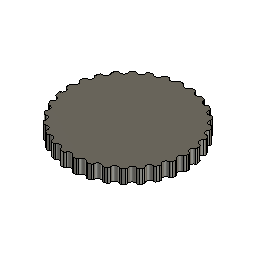
knob_ec12_3dprint (Autodesk Fusion 360 design; units mm, degrees)
Autodesk Fusion 360 part; units mm, degrees
sketch "Sketch1" plane through (0, 0, 0) normal (0, 0, 1) x (1, 0, 0)
  circle A0 centre (0, 0) radius 17.5
  circle A1 centre (0.0503, 17.4999) radius 1
  circle A2 centre (-3.5893, 17.128) radius 1
  circle A3 centre (-7.0719, 16.0074) radius 1
  circle A4 centre (-10.2455, 14.1873) radius 1
  circle A5 centre (-12.9713, 11.7471) radius 1
  circle A6 centre (-15.1302, 8.7935) radius 1
  circle A7 centre (-16.6279, 5.4556) radius 1
  circle A8 centre (-17.3988, 1.8793) radius 1
  circle A9 centre (-17.4093, -1.7792) radius 1
  circle A10 centre (-16.659, -5.3599) radius 1
  circle A11 centre (-15.1805, -8.7064) radius 1
  circle A12 centre (-13.0386, -11.6724) radius 1
  circle A13 centre (-10.3269, -14.1282) radius 1
  circle A14 centre (-7.1638, -15.9665) radius 1
  circle A15 centre (-3.6876, -17.1071) radius 1
  circle A16 centre (-0.0503, -17.4999) radius 1
  circle A17 centre (3.5893, -17.128) radius 1
  circle A18 centre (7.0719, -16.0074) radius 1
  circle A19 centre (10.2455, -14.1873) radius 1
  circle A20 centre (12.9713, -11.7471) radius 1
  circle A21 centre (15.1302, -8.7935) radius 1
  circle A22 centre (16.6279, -5.4556) radius 1
  circle A23 centre (17.3988, -1.8793) radius 1
  circle A24 centre (17.4093, 1.7792) radius 1
  circle A25 centre (16.659, 5.3599) radius 1
  circle A26 centre (15.1805, 8.7064) radius 1
  circle A27 centre (13.0386, 11.6724) radius 1
  circle A28 centre (10.3269, 14.1282) radius 1
  circle A29 centre (7.1638, 15.9665) radius 1
  circle A30 centre (3.6876, 17.1071) radius 1
  dimension "d1" = 35
  dimension "d12" = 2
  dimension "d14" = 360
  constraint coincident A0.centre origin
  constraint coincident A0 A1.centre
  measures "d1" diameter of A0
  measures "d12" diameter of A1
extrude "Extrude1" add sketch "Sketch1" along normal blind 4 contours A0 A1 A2 A3 A4 A5 A6 A7 A8 A9 A10 A11 A12 A13 A14 A15 A16 A17 A18 A19 A20 A21 A22 A23 A24 A25 A26 A27 A28 A29 A30
sketch "Sketch2" plane through (0, 0, 0) normal (0, 0, -1) x (1, 0, 0)
  circle A0 centre (0, 0) radius 3.025
  line L0 (2.2244, 2.05) -> (2.2244, -2.05)
  line L1 (0, 0) -> (2.2244, 2.05)
  line L2 (0, 0) -> (2.2244, -2.05)
  circle A1 centre (2.0774, 1.9145) radius 1.05
  circle A2 centre (2.0774, -1.9145) radius 1.05
  arc A3 (8.0641, -15.5313) -> (9.503, -14.695) centre (0, 0) ccw
  arc A4 (11.117, -13.5152) -> (9.503, -14.695) centre (10.3269, -14.1282) ccw
  arc A5 (11.117, -13.5152) -> (12.3506, -12.3981) centre (0, 0) ccw
  arc A6 (13.6841, -10.9085) -> (12.3506, -12.3981) centre (13.0386, -11.6724) ccw
  arc A7 (13.6841, -10.9085) -> (14.6584, -9.5593) centre (0, 0) ccw
  arc A8 (15.653, -7.8251) -> (14.6584, -9.5593) centre (15.1805, -8.7064) ccw
  arc A9 (15.653, -7.8251) -> (16.3256, -6.3028) centre (0, 0) ccw
  arc A10 (16.9379, -4.3996) -> (16.3256, -6.3028) centre (16.659, -5.3599) ccw
  arc A11 (16.9379, -4.3996) -> (17.2793, -2.7707) centre (0, 0) ccw
  arc A12 (17.4825, -0.7819) -> (17.2793, -2.7707) centre (17.4093, -1.7792) ccw
  arc A13 (17.4825, -0.7819) -> (17.4777, 0.8824) centre (0, 0) ccw
  arc A14 (17.2631, 2.87) -> (17.4777, 0.8824) centre (17.3988, 1.8793) ccw
  arc A15 (17.2631, 2.87) -> (16.9124, 4.4969) centre (0, 0) ccw
  arc A16 (16.2891, 6.3965) -> (16.9124, 4.4969) centre (16.6279, 5.4556) ccw
  arc A17 (16.2891, 6.3965) -> (15.6078, 7.9149) centre (0, 0) ccw
  arc A18 (14.6033, 9.6434) -> (15.6078, 7.9149) centre (15.1302, 8.7935) ccw
  arc A19 (14.6033, 9.6434) -> (13.6211, 10.987) centre (0, 0) ccw
  arc A20 (12.2792, 12.4688) -> (13.6211, 10.987) centre (12.9713, 11.7471) ccw
  arc A21 (12.2792, 12.4688) -> (11.0392, 13.5789) centre (0, 0) ccw
  arc A22 (9.4184, 14.7494) -> (11.0392, 13.5789) centre (10.2455, 14.1873) ccw
  arc A23 (9.4184, 14.7494) -> (7.9747, 15.5774) centre (0, 0) ccw
  arc A24 (6.146, 16.3852) -> (7.9747, 15.5774) centre (7.0719, 16.0074) ccw
  arc A25 (6.146, 16.3852) -> (4.5617, 16.895) centre (0, 0) ccw
  arc A26 (2.605, 17.305) -> (4.5617, 16.895) centre (3.5893, 17.128) ccw
  arc A27 (2.605, 17.305) -> (0.9494, 17.4742) centre (0, 0) ccw
  arc A28 (-1.0498, 17.4685) -> (0.9494, 17.4742) centre (-0.0503, 17.4999) ccw
  arc A29 (-1.0498, 17.4685) -> (-2.7045, 17.2898) centre (0, 0) ccw
  arc A30 (-4.6588, 16.8685) -> (-2.7045, 17.2898) centre (-3.6876, 17.1071) ccw
  arc A31 (-4.6588, 16.8685) -> (-6.2401, 16.3497) centre (0, 0) ccw
  arc A32 (-8.0641, 15.5313) -> (-6.2401, 16.3497) centre (-7.1638, 15.9665) ccw
  arc A33 (-8.0641, 15.5313) -> (-9.503, 14.695) centre (0, 0) ccw
  arc A34 (-11.117, 13.5152) -> (-9.503, 14.695) centre (-10.3269, 14.1282) ccw
  arc A35 (-11.117, 13.5152) -> (-12.3506, 12.3981) centre (0, 0) ccw
  arc A36 (-13.6841, 10.9085) -> (-12.3506, 12.3981) centre (-13.0386, 11.6724) ccw
  arc A37 (-13.6841, 10.9085) -> (-14.6584, 9.5593) centre (0, 0) ccw
  arc A38 (-15.653, 7.8251) -> (-14.6584, 9.5593) centre (-15.1805, 8.7064) ccw
  arc A39 (-15.653, 7.8251) -> (-16.3256, 6.3028) centre (0, 0) ccw
  arc A40 (-16.9379, 4.3996) -> (-16.3256, 6.3028) centre (-16.659, 5.3599) ccw
  arc A41 (-16.9379, 4.3996) -> (-17.2793, 2.7707) centre (0, 0) ccw
  arc A42 (-17.4825, 0.7819) -> (-17.2793, 2.7707) centre (-17.4093, 1.7792) ccw
  arc A43 (-17.4825, 0.7819) -> (-17.4777, -0.8824) centre (0, 0) ccw
  arc A44 (-17.2631, -2.87) -> (-17.4777, -0.8824) centre (-17.3988, -1.8793) ccw
  arc A45 (-17.2631, -2.87) -> (-16.9124, -4.4969) centre (0, 0) ccw
  arc A46 (-16.2891, -6.3965) -> (-16.9124, -4.4969) centre (-16.6279, -5.4556) ccw
  arc A47 (-16.2891, -6.3965) -> (-15.6078, -7.9149) centre (0, 0) ccw
  arc A48 (-14.6033, -9.6434) -> (-15.6078, -7.9149) centre (-15.1302, -8.7935) ccw
  arc A49 (-14.6033, -9.6434) -> (-13.6211, -10.987) centre (0, 0) ccw
  arc A50 (-12.2792, -12.4688) -> (-13.6211, -10.987) centre (-12.9713, -11.7471) ccw
  arc A51 (-12.2792, -12.4688) -> (-11.0392, -13.5789) centre (0, 0) ccw
  arc A52 (-9.4184, -14.7494) -> (-11.0392, -13.5789) centre (-10.2455, -14.1873) ccw
  arc A53 (-9.4184, -14.7494) -> (-7.9747, -15.5774) centre (0, 0) ccw
  arc A54 (-6.146, -16.3852) -> (-7.9747, -15.5774) centre (-7.0719, -16.0074) ccw
  arc A55 (-6.146, -16.3852) -> (-4.5617, -16.895) centre (0, 0) ccw
  arc A56 (-2.605, -17.305) -> (-4.5617, -16.895) centre (-3.5893, -17.128) ccw
  arc A57 (-2.605, -17.305) -> (-0.9494, -17.4742) centre (0, 0) ccw
  arc A58 (1.0498, -17.4685) -> (-0.9494, -17.4742) centre (0.0503, -17.4999) ccw
  arc A59 (1.0498, -17.4685) -> (2.7045, -17.2898) centre (0, 0) ccw
  arc A60 (4.6588, -16.8685) -> (2.7045, -17.2898) centre (3.6876, -17.1071) ccw
  arc A61 (4.6588, -16.8685) -> (6.2401, -16.3497) centre (0, 0) ccw
  arc A62 (8.0641, -15.5313) -> (6.2401, -16.3497) centre (7.1638, -15.9665) ccw
  dimension "d4" = 6.05
  dimension "d5" = 4.1
  dimension "d6" = 2.1
  dimension "d7" = 0.2
  dimension "d8" = 2.1
  dimension "d9" = 0.2
  constraint concentric A0 A3
  constraint coincident A0 L0.start
  constraint coincident A0 L0.end
  constraint vertical L0
  constraint coincident A0.centre L1.start
  constraint coincident L1 A1.centre
  constraint coincident L2 A2.centre
  measures "d4" diameter of A0
  measures "d5" distance of L0.start L0.end
  measures "d6" diameter of A1
  measures "d7" distance of L0.start A1.centre
  measures "d8" diameter of A2
  measures "d9" distance of L0.end A2.centre
extrude "Extrude2" cut sketch "Sketch2" against normal blind 2.6 contours A0 L0 A1 | A0 A1 | A0 A2 | A0 L0 A2 | A0 L1 A1 | L0 L1 A1 | L0 L1 L2 A1 A2 | L0 L2 A2 | A0 L2 A2 | A0 L1 L2 A1 A2
sketch "Sketch3" plane through (0, 0, 0) normal (0, 0, -1) x (1, 0, 0)
  arc A0 (1.3746, 2.6946) -> (1.3746, -2.6946) centre (0, 0) ccw
  arc A1 (2.2244, 0.8748) -> (1.3746, 2.6946) centre (2.0774, 1.9145) ccw
  line L0 (2.2244, 0.8748) -> (2.2244, -0.8748)
  arc A2 (1.3746, -2.6946) -> (2.2244, -0.8748) centre (2.0774, -1.9145) ccw
  arc A3 (8.0641, -15.5313) -> (9.503, -14.695) centre (0, 0) ccw
  arc A4 (11.117, -13.5152) -> (9.503, -14.695) centre (10.3269, -14.1282) ccw
  arc A5 (11.117, -13.5152) -> (12.3506, -12.3981) centre (0, 0) ccw
  arc A6 (13.6841, -10.9085) -> (12.3506, -12.3981) centre (13.0386, -11.6724) ccw
  arc A7 (13.6841, -10.9085) -> (14.6584, -9.5593) centre (0, 0) ccw
  arc A8 (15.653, -7.8251) -> (14.6584, -9.5593) centre (15.1805, -8.7064) ccw
  arc A9 (15.653, -7.8251) -> (16.3256, -6.3028) centre (0, 0) ccw
  arc A10 (16.9379, -4.3996) -> (16.3256, -6.3028) centre (16.659, -5.3599) ccw
  arc A11 (16.9379, -4.3996) -> (17.2793, -2.7707) centre (0, 0) ccw
  arc A12 (17.4825, -0.7819) -> (17.2793, -2.7707) centre (17.4093, -1.7792) ccw
  arc A13 (17.4825, -0.7819) -> (17.4777, 0.8824) centre (0, 0) ccw
  arc A14 (17.2631, 2.87) -> (17.4777, 0.8824) centre (17.3988, 1.8793) ccw
  arc A15 (17.2631, 2.87) -> (16.9124, 4.4969) centre (0, 0) ccw
  arc A16 (16.2891, 6.3965) -> (16.9124, 4.4969) centre (16.6279, 5.4556) ccw
  arc A17 (16.2891, 6.3965) -> (15.6078, 7.9149) centre (0, 0) ccw
  arc A18 (14.6033, 9.6434) -> (15.6078, 7.9149) centre (15.1302, 8.7935) ccw
  arc A19 (14.6033, 9.6434) -> (13.6211, 10.987) centre (0, 0) ccw
  arc A20 (12.2792, 12.4688) -> (13.6211, 10.987) centre (12.9713, 11.7471) ccw
  arc A21 (12.2792, 12.4688) -> (11.0392, 13.5789) centre (0, 0) ccw
  arc A22 (9.4184, 14.7494) -> (11.0392, 13.5789) centre (10.2455, 14.1873) ccw
  arc A23 (9.4184, 14.7494) -> (7.9747, 15.5774) centre (0, 0) ccw
  arc A24 (6.146, 16.3852) -> (7.9747, 15.5774) centre (7.0719, 16.0074) ccw
  arc A25 (6.146, 16.3852) -> (4.5617, 16.895) centre (0, 0) ccw
  arc A26 (2.605, 17.305) -> (4.5617, 16.895) centre (3.5893, 17.128) ccw
  arc A27 (2.605, 17.305) -> (0.9494, 17.4742) centre (0, 0) ccw
  arc A28 (-1.0498, 17.4685) -> (0.9494, 17.4742) centre (-0.0503, 17.4999) ccw
  arc A29 (-1.0498, 17.4685) -> (-2.7045, 17.2898) centre (0, 0) ccw
  arc A30 (-4.6588, 16.8685) -> (-2.7045, 17.2898) centre (-3.6876, 17.1071) ccw
  arc A31 (-4.6588, 16.8685) -> (-6.2401, 16.3497) centre (0, 0) ccw
  arc A32 (-8.0641, 15.5313) -> (-6.2401, 16.3497) centre (-7.1638, 15.9665) ccw
  arc A33 (-8.0641, 15.5313) -> (-9.503, 14.695) centre (0, 0) ccw
  arc A34 (-11.117, 13.5152) -> (-9.503, 14.695) centre (-10.3269, 14.1282) ccw
  arc A35 (-11.117, 13.5152) -> (-12.3506, 12.3981) centre (0, 0) ccw
  arc A36 (-13.6841, 10.9085) -> (-12.3506, 12.3981) centre (-13.0386, 11.6724) ccw
  arc A37 (-13.6841, 10.9085) -> (-14.6584, 9.5593) centre (0, 0) ccw
  arc A38 (-15.653, 7.8251) -> (-14.6584, 9.5593) centre (-15.1805, 8.7064) ccw
  arc A39 (-15.653, 7.8251) -> (-16.3256, 6.3028) centre (0, 0) ccw
  arc A40 (-16.9379, 4.3996) -> (-16.3256, 6.3028) centre (-16.659, 5.3599) ccw
  arc A41 (-16.9379, 4.3996) -> (-17.2793, 2.7707) centre (0, 0) ccw
  arc A42 (-17.4825, 0.7819) -> (-17.2793, 2.7707) centre (-17.4093, 1.7792) ccw
  arc A43 (-17.4825, 0.7819) -> (-17.4777, -0.8824) centre (0, 0) ccw
  arc A44 (-17.2631, -2.87) -> (-17.4777, -0.8824) centre (-17.3988, -1.8793) ccw
  arc A45 (-17.2631, -2.87) -> (-16.9124, -4.4969) centre (0, 0) ccw
  arc A46 (-16.2891, -6.3965) -> (-16.9124, -4.4969) centre (-16.6279, -5.4556) ccw
  arc A47 (-16.2891, -6.3965) -> (-15.6078, -7.9149) centre (0, 0) ccw
  arc A48 (-14.6033, -9.6434) -> (-15.6078, -7.9149) centre (-15.1302, -8.7935) ccw
  arc A49 (-14.6033, -9.6434) -> (-13.6211, -10.987) centre (0, 0) ccw
  arc A50 (-12.2792, -12.4688) -> (-13.6211, -10.987) centre (-12.9713, -11.7471) ccw
  arc A51 (-12.2792, -12.4688) -> (-11.0392, -13.5789) centre (0, 0) ccw
  arc A52 (-9.4184, -14.7494) -> (-11.0392, -13.5789) centre (-10.2455, -14.1873) ccw
  arc A53 (-9.4184, -14.7494) -> (-7.9747, -15.5774) centre (0, 0) ccw
  arc A54 (-6.146, -16.3852) -> (-7.9747, -15.5774) centre (-7.0719, -16.0074) ccw
  arc A55 (-6.146, -16.3852) -> (-4.5617, -16.895) centre (0, 0) ccw
  arc A56 (-2.605, -17.305) -> (-4.5617, -16.895) centre (-3.5893, -17.128) ccw
  arc A57 (-2.605, -17.305) -> (-0.9494, -17.4742) centre (0, 0) ccw
  arc A58 (1.0498, -17.4685) -> (-0.9494, -17.4742) centre (0.0503, -17.4999) ccw
  arc A59 (1.0498, -17.4685) -> (2.7045, -17.2898) centre (0, 0) ccw
  arc A60 (4.6588, -16.8685) -> (2.7045, -17.2898) centre (3.6876, -17.1071) ccw
  arc A61 (4.6588, -16.8685) -> (6.2401, -16.3497) centre (0, 0) ccw
  arc A62 (8.0641, -15.5313) -> (6.2401, -16.3497) centre (7.1638, -15.9665) ccw
  circle A63 centre (0, 0) radius 5
  constraint concentric A0 A63
sketch "Sketch4" plane through (0, 0, 0) normal (0, 0, -1) x (1, 0, 0)
  arc A0 (1.3746, 2.6946) -> (1.3746, -2.6946) centre (0, 0) ccw
  arc A1 (2.2244, 0.8748) -> (1.3746, 2.6946) centre (2.0774, 1.9145) ccw
  line L0 (2.2244, 0.8748) -> (2.2244, -0.8748)
  arc A2 (1.3746, -2.6946) -> (2.2244, -0.8748) centre (2.0774, -1.9145) ccw
  arc A3 (8.0641, -15.5313) -> (9.503, -14.695) centre (0, 0) ccw
  arc A4 (11.117, -13.5152) -> (9.503, -14.695) centre (10.3269, -14.1282) ccw
  arc A5 (11.117, -13.5152) -> (12.3506, -12.3981) centre (0, 0) ccw
  arc A6 (13.6841, -10.9085) -> (12.3506, -12.3981) centre (13.0386, -11.6724) ccw
  arc A7 (13.6841, -10.9085) -> (14.6584, -9.5593) centre (0, 0) ccw
  arc A8 (15.653, -7.8251) -> (14.6584, -9.5593) centre (15.1805, -8.7064) ccw
  arc A9 (15.653, -7.8251) -> (16.3256, -6.3028) centre (0, 0) ccw
  arc A10 (16.9379, -4.3996) -> (16.3256, -6.3028) centre (16.659, -5.3599) ccw
  arc A11 (16.9379, -4.3996) -> (17.2793, -2.7707) centre (0, 0) ccw
  arc A12 (17.4825, -0.7819) -> (17.2793, -2.7707) centre (17.4093, -1.7792) ccw
  arc A13 (17.4825, -0.7819) -> (17.4777, 0.8824) centre (0, 0) ccw
  arc A14 (17.2631, 2.87) -> (17.4777, 0.8824) centre (17.3988, 1.8793) ccw
  arc A15 (17.2631, 2.87) -> (16.9124, 4.4969) centre (0, 0) ccw
  arc A16 (16.2891, 6.3965) -> (16.9124, 4.4969) centre (16.6279, 5.4556) ccw
  arc A17 (16.2891, 6.3965) -> (15.6078, 7.9149) centre (0, 0) ccw
  arc A18 (14.6033, 9.6434) -> (15.6078, 7.9149) centre (15.1302, 8.7935) ccw
  arc A19 (14.6033, 9.6434) -> (13.6211, 10.987) centre (0, 0) ccw
  arc A20 (12.2792, 12.4688) -> (13.6211, 10.987) centre (12.9713, 11.7471) ccw
  arc A21 (12.2792, 12.4688) -> (11.0392, 13.5789) centre (0, 0) ccw
  arc A22 (9.4184, 14.7494) -> (11.0392, 13.5789) centre (10.2455, 14.1873) ccw
  arc A23 (9.4184, 14.7494) -> (7.9747, 15.5774) centre (0, 0) ccw
  arc A24 (6.146, 16.3852) -> (7.9747, 15.5774) centre (7.0719, 16.0074) ccw
  arc A25 (6.146, 16.3852) -> (4.5617, 16.895) centre (0, 0) ccw
  arc A26 (2.605, 17.305) -> (4.5617, 16.895) centre (3.5893, 17.128) ccw
  arc A27 (2.605, 17.305) -> (0.9494, 17.4742) centre (0, 0) ccw
  arc A28 (-1.0498, 17.4685) -> (0.9494, 17.4742) centre (-0.0503, 17.4999) ccw
  arc A29 (-1.0498, 17.4685) -> (-2.7045, 17.2898) centre (0, 0) ccw
  arc A30 (-4.6588, 16.8685) -> (-2.7045, 17.2898) centre (-3.6876, 17.1071) ccw
  arc A31 (-4.6588, 16.8685) -> (-6.2401, 16.3497) centre (0, 0) ccw
  arc A32 (-8.0641, 15.5313) -> (-6.2401, 16.3497) centre (-7.1638, 15.9665) ccw
  arc A33 (-8.0641, 15.5313) -> (-9.503, 14.695) centre (0, 0) ccw
  arc A34 (-11.117, 13.5152) -> (-9.503, 14.695) centre (-10.3269, 14.1282) ccw
  arc A35 (-11.117, 13.5152) -> (-12.3506, 12.3981) centre (0, 0) ccw
  arc A36 (-13.6841, 10.9085) -> (-12.3506, 12.3981) centre (-13.0386, 11.6724) ccw
  arc A37 (-13.6841, 10.9085) -> (-14.6584, 9.5593) centre (0, 0) ccw
  arc A38 (-15.653, 7.8251) -> (-14.6584, 9.5593) centre (-15.1805, 8.7064) ccw
  arc A39 (-15.653, 7.8251) -> (-16.3256, 6.3028) centre (0, 0) ccw
  arc A40 (-16.9379, 4.3996) -> (-16.3256, 6.3028) centre (-16.659, 5.3599) ccw
  arc A41 (-16.9379, 4.3996) -> (-17.2793, 2.7707) centre (0, 0) ccw
  arc A42 (-17.4825, 0.7819) -> (-17.2793, 2.7707) centre (-17.4093, 1.7792) ccw
  arc A43 (-17.4825, 0.7819) -> (-17.4777, -0.8824) centre (0, 0) ccw
  arc A44 (-17.2631, -2.87) -> (-17.4777, -0.8824) centre (-17.3988, -1.8793) ccw
  arc A45 (-17.2631, -2.87) -> (-16.9124, -4.4969) centre (0, 0) ccw
  arc A46 (-16.2891, -6.3965) -> (-16.9124, -4.4969) centre (-16.6279, -5.4556) ccw
  arc A47 (-16.2891, -6.3965) -> (-15.6078, -7.9149) centre (0, 0) ccw
  arc A48 (-14.6033, -9.6434) -> (-15.6078, -7.9149) centre (-15.1302, -8.7935) ccw
  arc A49 (-14.6033, -9.6434) -> (-13.6211, -10.987) centre (0, 0) ccw
  arc A50 (-12.2792, -12.4688) -> (-13.6211, -10.987) centre (-12.9713, -11.7471) ccw
  arc A51 (-12.2792, -12.4688) -> (-11.0392, -13.5789) centre (0, 0) ccw
  arc A52 (-9.4184, -14.7494) -> (-11.0392, -13.5789) centre (-10.2455, -14.1873) ccw
  arc A53 (-9.4184, -14.7494) -> (-7.9747, -15.5774) centre (0, 0) ccw
  arc A54 (-6.146, -16.3852) -> (-7.9747, -15.5774) centre (-7.0719, -16.0074) ccw
  arc A55 (-6.146, -16.3852) -> (-4.5617, -16.895) centre (0, 0) ccw
  arc A56 (-2.605, -17.305) -> (-4.5617, -16.895) centre (-3.5893, -17.128) ccw
  arc A57 (-2.605, -17.305) -> (-0.9494, -17.4742) centre (0, 0) ccw
  arc A58 (1.0498, -17.4685) -> (-0.9494, -17.4742) centre (0.0503, -17.4999) ccw
  arc A59 (1.0498, -17.4685) -> (2.7045, -17.2898) centre (0, 0) ccw
  arc A60 (4.6588, -16.8685) -> (2.7045, -17.2898) centre (3.6876, -17.1071) ccw
  arc A61 (4.6588, -16.8685) -> (6.2401, -16.3497) centre (0, 0) ccw
  arc A62 (8.0641, -15.5313) -> (6.2401, -16.3497) centre (7.1638, -15.9665) ccw
  circle A63 centre (0, 0) radius 11
  circle A64 centre (0, -11) radius 2.5
  circle A65 centre (0, 11) radius 2.5
  circle A66 centre (-11, 0) radius 2.5
  circle A67 centre (11, 0) radius 2.5
  point P0 (-0.3876, 0)
  dimension "d17" = 22
  dimension "d39" = 5
  dimension "d40" = 5
  dimension "d41" = 5
  dimension "d42" = 5
  dimension "d45" = 2.612
  dimension "d46" = 0.3876
  constraint concentric A0 A63
  constraint coincident A63 A64.centre
  constraint coincident A63 A65.centre
  constraint coincident A63 A66.centre
  constraint coincident A63 A67.centre
  measures "d17" diameter of A63
  measures "d39" diameter of A64
  measures "d40" diameter of A65
  measures "d41" diameter of A66
  measures "d42" diameter of A67
  measures "d45" distance of L0 P0
  measures "d46" distance of A0.centre P0
sketch "Sketch10" plane through (0, 0, 0) normal (0, 0, 1) x (-1, 0, 0)
  circle A0 centre (5, 8.6603) radius 4.3589
  circle A1 centre (5, -8.6603) radius 4.3589
  circle A2 centre (-10, 0) radius 4.3589
  arc A3 (-9.503, -14.695) -> (-8.0641, -15.5313) centre (0, 0) ccw
  arc A4 (-6.2401, -16.3497) -> (-8.0641, -15.5313) centre (-7.1638, -15.9665) ccw
  arc A5 (-6.2401, -16.3497) -> (-4.6588, -16.8685) centre (0, 0) ccw
  arc A6 (-2.7045, -17.2898) -> (-4.6588, -16.8685) centre (-3.6876, -17.1071) ccw
  arc A7 (-2.7045, -17.2898) -> (-1.0498, -17.4685) centre (0, 0) ccw
  arc A8 (0.9494, -17.4742) -> (-1.0498, -17.4685) centre (-0.0503, -17.4999) ccw
  arc A9 (0.9494, -17.4742) -> (2.605, -17.305) centre (0, 0) ccw
  arc A10 (4.5617, -16.895) -> (2.605, -17.305) centre (3.5893, -17.128) ccw
  arc A11 (4.5617, -16.895) -> (6.146, -16.3852) centre (0, 0) ccw
  arc A12 (7.9747, -15.5774) -> (6.146, -16.3852) centre (7.0719, -16.0074) ccw
  arc A13 (7.9747, -15.5774) -> (9.4184, -14.7494) centre (0, 0) ccw
  arc A14 (11.0392, -13.5789) -> (9.4184, -14.7494) centre (10.2455, -14.1873) ccw
  arc A15 (11.0392, -13.5789) -> (12.2792, -12.4688) centre (0, 0) ccw
  arc A16 (13.6211, -10.987) -> (12.2792, -12.4688) centre (12.9713, -11.7471) ccw
  arc A17 (13.6211, -10.987) -> (14.6033, -9.6434) centre (0, 0) ccw
  arc A18 (15.6078, -7.9149) -> (14.6033, -9.6434) centre (15.1302, -8.7935) ccw
  arc A19 (15.6078, -7.9149) -> (16.2891, -6.3965) centre (0, 0) ccw
  arc A20 (16.9124, -4.4969) -> (16.2891, -6.3965) centre (16.6279, -5.4556) ccw
  arc A21 (16.9124, -4.4969) -> (17.2631, -2.87) centre (0, 0) ccw
  arc A22 (17.4777, -0.8824) -> (17.2631, -2.87) centre (17.3988, -1.8793) ccw
  arc A23 (17.4777, -0.8824) -> (17.4825, 0.7819) centre (0, 0) ccw
  arc A24 (17.2793, 2.7707) -> (17.4825, 0.7819) centre (17.4093, 1.7792) ccw
  arc A25 (17.2793, 2.7707) -> (16.9379, 4.3996) centre (0, 0) ccw
  arc A26 (16.3256, 6.3028) -> (16.9379, 4.3996) centre (16.659, 5.3599) ccw
  arc A27 (16.3256, 6.3028) -> (15.653, 7.8251) centre (0, 0) ccw
  arc A28 (14.6584, 9.5593) -> (15.653, 7.8251) centre (15.1805, 8.7064) ccw
  arc A29 (14.6584, 9.5593) -> (13.6841, 10.9085) centre (0, 0) ccw
  arc A30 (12.3506, 12.3981) -> (13.6841, 10.9085) centre (13.0386, 11.6724) ccw
  arc A31 (12.3506, 12.3981) -> (11.117, 13.5152) centre (0, 0) ccw
  arc A32 (9.503, 14.695) -> (11.117, 13.5152) centre (10.3269, 14.1282) ccw
  arc A33 (9.503, 14.695) -> (8.0641, 15.5313) centre (0, 0) ccw
  arc A34 (6.2401, 16.3497) -> (8.0641, 15.5313) centre (7.1638, 15.9665) ccw
  arc A35 (6.2401, 16.3497) -> (4.6588, 16.8685) centre (0, 0) ccw
  arc A36 (2.7045, 17.2898) -> (4.6588, 16.8685) centre (3.6876, 17.1071) ccw
  arc A37 (2.7045, 17.2898) -> (1.0498, 17.4685) centre (0, 0) ccw
  arc A38 (-0.9494, 17.4742) -> (1.0498, 17.4685) centre (0.0503, 17.4999) ccw
  arc A39 (-0.9494, 17.4742) -> (-2.605, 17.305) centre (0, 0) ccw
  arc A40 (-4.5617, 16.895) -> (-2.605, 17.305) centre (-3.5893, 17.128) ccw
  arc A41 (-4.5617, 16.895) -> (-6.146, 16.3852) centre (0, 0) ccw
  arc A42 (-7.9747, 15.5774) -> (-6.146, 16.3852) centre (-7.0719, 16.0074) ccw
  arc A43 (-7.9747, 15.5774) -> (-9.4184, 14.7494) centre (0, 0) ccw
  arc A44 (-11.0392, 13.5789) -> (-9.4184, 14.7494) centre (-10.2455, 14.1873) ccw
  arc A45 (-11.0392, 13.5789) -> (-12.2792, 12.4688) centre (0, 0) ccw
  arc A46 (-13.6211, 10.987) -> (-12.2792, 12.4688) centre (-12.9713, 11.7471) ccw
  arc A47 (-13.6211, 10.987) -> (-14.6033, 9.6434) centre (0, 0) ccw
  arc A48 (-15.6078, 7.9149) -> (-14.6033, 9.6434) centre (-15.1302, 8.7935) ccw
  arc A49 (-15.6078, 7.9149) -> (-16.2891, 6.3965) centre (0, 0) ccw
  arc A50 (-16.9124, 4.4969) -> (-16.2891, 6.3965) centre (-16.6279, 5.4556) ccw
  arc A51 (-16.9124, 4.4969) -> (-17.2631, 2.87) centre (0, 0) ccw
  arc A52 (-17.4777, 0.8824) -> (-17.2631, 2.87) centre (-17.3988, 1.8793) ccw
  arc A53 (-17.4777, 0.8824) -> (-17.4825, -0.7819) centre (0, 0) ccw
  arc A54 (-17.2793, -2.7707) -> (-17.4825, -0.7819) centre (-17.4093, -1.7792) ccw
  arc A55 (-17.2793, -2.7707) -> (-16.9379, -4.3996) centre (0, 0) ccw
  arc A56 (-16.3256, -6.3028) -> (-16.9379, -4.3996) centre (-16.659, -5.3599) ccw
  arc A57 (-16.3256, -6.3028) -> (-15.653, -7.8251) centre (0, 0) ccw
  arc A58 (-14.6584, -9.5593) -> (-15.653, -7.8251) centre (-15.1805, -8.7064) ccw
  arc A59 (-14.6584, -9.5593) -> (-13.6841, -10.9085) centre (0, 0) ccw
  arc A60 (-12.3506, -12.3981) -> (-13.6841, -10.9085) centre (-13.0386, -11.6724) ccw
  arc A61 (-12.3506, -12.3981) -> (-11.117, -13.5152) centre (0, 0) ccw
  arc A62 (-9.503, -14.695) -> (-11.117, -13.5152) centre (-10.3269, -14.1282) ccw
  arc A63 (-1.3746, -2.6946) -> (-1.3746, 2.6946) centre (0, 0) ccw
  arc A64 (-1.3746, 2.6946) -> (-2.2244, 0.8748) centre (-2.0774, 1.9145) ccw
  line L0 (-2.2244, 0.8748) -> (-2.2244, -0.8748)
  arc A65 (-2.2244, -0.8748) -> (-1.3746, -2.6946) centre (-2.0774, -1.9145) ccw
  arc A66 (-9.503, -14.695) -> (-8.0641, -15.5313) centre (0, 0) ccw
  arc A67 (-9.503, -14.695) -> (-11.117, -13.5152) centre (-10.3269, -14.1282) ccw
  arc A68 (-12.3506, -12.3981) -> (-11.117, -13.5152) centre (0, 0) ccw
  arc A69 (-12.3506, -12.3981) -> (-13.6841, -10.9085) centre (-13.0386, -11.6724) ccw
  arc A70 (-14.6584, -9.5593) -> (-13.6841, -10.9085) centre (0, 0) ccw
  arc A71 (-14.6584, -9.5593) -> (-15.653, -7.8251) centre (-15.1805, -8.7064) ccw
  arc A72 (-16.3256, -6.3028) -> (-15.653, -7.8251) centre (0, 0) ccw
  arc A73 (-16.3256, -6.3028) -> (-16.9379, -4.3996) centre (-16.659, -5.3599) ccw
  arc A74 (-17.2793, -2.7707) -> (-16.9379, -4.3996) centre (0, 0) ccw
  arc A75 (-17.2793, -2.7707) -> (-17.4825, -0.7819) centre (-17.4093, -1.7792) ccw
  arc A76 (-17.4777, 0.8824) -> (-17.4825, -0.7819) centre (0, 0) ccw
  arc A77 (-17.4777, 0.8824) -> (-17.2631, 2.87) centre (-17.3988, 1.8793) ccw
  arc A78 (-16.9124, 4.4969) -> (-17.2631, 2.87) centre (0, 0) ccw
  arc A79 (-16.9124, 4.4969) -> (-16.2891, 6.3965) centre (-16.6279, 5.4556) ccw
  arc A80 (-15.6078, 7.9149) -> (-16.2891, 6.3965) centre (0, 0) ccw
  arc A81 (-15.6078, 7.9149) -> (-14.6033, 9.6434) centre (-15.1302, 8.7935) ccw
  arc A82 (-13.6211, 10.987) -> (-14.6033, 9.6434) centre (0, 0) ccw
  arc A83 (-13.6211, 10.987) -> (-12.2792, 12.4688) centre (-12.9713, 11.7471) ccw
  arc A84 (-11.0392, 13.5789) -> (-12.2792, 12.4688) centre (0, 0) ccw
  arc A85 (-11.0392, 13.5789) -> (-9.4184, 14.7494) centre (-10.2455, 14.1873) ccw
  arc A86 (-7.9747, 15.5774) -> (-9.4184, 14.7494) centre (0, 0) ccw
  arc A87 (-7.9747, 15.5774) -> (-6.146, 16.3852) centre (-7.0719, 16.0074) ccw
  arc A88 (-4.5617, 16.895) -> (-6.146, 16.3852) centre (0, 0) ccw
  arc A89 (-4.5617, 16.895) -> (-2.605, 17.305) centre (-3.5893, 17.128) ccw
  arc A90 (-0.9494, 17.4742) -> (-2.605, 17.305) centre (0, 0) ccw
  arc A91 (-0.9494, 17.4742) -> (1.0498, 17.4685) centre (0.0503, 17.4999) ccw
  arc A92 (2.7045, 17.2898) -> (1.0498, 17.4685) centre (0, 0) ccw
  arc A93 (2.7045, 17.2898) -> (4.6588, 16.8685) centre (3.6876, 17.1071) ccw
  arc A94 (6.2401, 16.3497) -> (4.6588, 16.8685) centre (0, 0) ccw
  arc A95 (6.2401, 16.3497) -> (8.0641, 15.5313) centre (7.1638, 15.9665) ccw
  arc A96 (9.503, 14.695) -> (8.0641, 15.5313) centre (0, 0) ccw
  arc A97 (9.503, 14.695) -> (11.117, 13.5152) centre (10.3269, 14.1282) ccw
  arc A98 (12.3506, 12.3981) -> (11.117, 13.5152) centre (0, 0) ccw
  arc A99 (12.3506, 12.3981) -> (13.6841, 10.9085) centre (13.0386, 11.6724) ccw
  arc A100 (14.6584, 9.5593) -> (13.6841, 10.9085) centre (0, 0) ccw
  arc A101 (14.6584, 9.5593) -> (15.653, 7.8251) centre (15.1805, 8.7064) ccw
  arc A102 (16.3256, 6.3028) -> (15.653, 7.8251) centre (0, 0) ccw
  arc A103 (16.3256, 6.3028) -> (16.9379, 4.3996) centre (16.659, 5.3599) ccw
  arc A104 (17.2793, 2.7707) -> (16.9379, 4.3996) centre (0, 0) ccw
  arc A105 (17.2793, 2.7707) -> (17.4825, 0.7819) centre (17.4093, 1.7792) ccw
  arc A106 (17.4777, -0.8824) -> (17.4825, 0.7819) centre (0, 0) ccw
  arc A107 (17.4777, -0.8824) -> (17.2631, -2.87) centre (17.3988, -1.8793) ccw
  arc A108 (16.9124, -4.4969) -> (17.2631, -2.87) centre (0, 0) ccw
  arc A109 (16.9124, -4.4969) -> (16.2891, -6.3965) centre (16.6279, -5.4556) ccw
  arc A110 (15.6078, -7.9149) -> (16.2891, -6.3965) centre (0, 0) ccw
  arc A111 (15.6078, -7.9149) -> (14.6033, -9.6434) centre (15.1302, -8.7935) ccw
  arc A112 (13.6211, -10.987) -> (14.6033, -9.6434) centre (0, 0) ccw
  arc A113 (13.6211, -10.987) -> (12.2792, -12.4688) centre (12.9713, -11.7471) ccw
  arc A114 (11.0392, -13.5789) -> (12.2792, -12.4688) centre (0, 0) ccw
  arc A115 (11.0392, -13.5789) -> (9.4184, -14.7494) centre (10.2455, -14.1873) ccw
  arc A116 (7.9747, -15.5774) -> (9.4184, -14.7494) centre (0, 0) ccw
  arc A117 (7.9747, -15.5774) -> (6.146, -16.3852) centre (7.0719, -16.0074) ccw
  arc A118 (4.5617, -16.895) -> (6.146, -16.3852) centre (0, 0) ccw
  arc A119 (4.5617, -16.895) -> (2.605, -17.305) centre (3.5893, -17.128) ccw
  arc A120 (0.9494, -17.4742) -> (2.605, -17.305) centre (0, 0) ccw
  arc A121 (0.9494, -17.4742) -> (-1.0498, -17.4685) centre (-0.0503, -17.4999) ccw
  arc A122 (-2.7045, -17.2898) -> (-1.0498, -17.4685) centre (0, 0) ccw
  arc A123 (-2.7045, -17.2898) -> (-4.6588, -16.8685) centre (-3.6876, -17.1071) ccw
  arc A124 (-6.2401, -16.3497) -> (-4.6588, -16.8685) centre (0, 0) ccw
  arc A125 (-6.2401, -16.3497) -> (-8.0641, -15.5313) centre (-7.1638, -15.9665) ccw
  point P0 (17, 17)
fillet "Fillet1" radius 0.5 60 edges at (-11.117, -13.5152, 2) (-12.3506, -12.3981, 2) (-13.6841, -10.9085, 2) (-14.6584, -9.5593, 2) (-15.653, -7.8251, 2) (-16.3256, -6.3028, 2) (-16.9379, -4.3996, 2) (-17.2793, -2.7707, 2) (-17.4825, -0.7819, 2) (-9.503, -14.695, 2) (-8.0641, -15.5313, 2) (-6.2401, -16.3497, 2) (-4.6588, -16.8685, 2) (-2.7045, -17.2898, 2) (-1.0498, -17.4685, 2) (0.9494, -17.4742, 2) (2.605, -17.305, 2) (4.5617, -16.895, 2) (6.146, -16.3852, 2) (7.9747, -15.5774, 2) (9.4184, -14.7494, 2) (11.0392, -13.5789, 2) (12.2792, -12.4688, 2) (13.6211, -10.987, 2) (14.6033, -9.6434, 2) (15.6078, -7.9149, 2) (16.2891, -6.3965, 2) (16.9124, -4.4969, 2) (17.2631, -2.87, 2) (17.4777, -0.8824, 2) (17.4825, 0.7819, 2) (17.2793, 2.7707, 2) (16.9379, 4.3996, 2) (16.3256, 6.3028, 2) (15.653, 7.8251, 2) (14.6584, 9.5593, 2) (13.6841, 10.9085, 2) (12.3506, 12.3981, 2) (11.117, 13.5152, 2) (9.503, 14.695, 2) (8.0641, 15.5313, 2) (6.2401, 16.3497, 2) (4.6588, 16.8685, 2) (2.7045, 17.2898, 2) (1.0498, 17.4685, 2) (-0.9494, 17.4742, 2) (-2.605, 17.305, 2) (-4.5617, 16.895, 2) (-6.146, 16.3852, 2) (-7.9747, 15.5774, 2) (-9.4184, 14.7494, 2) (-11.0392, 13.5789, 2) (-12.2792, 12.4688, 2) (-13.6211, 10.987, 2) (-14.6033, 9.6434, 2) (-15.6078, 7.9149, 2) (-16.2891, 6.3965, 2) (-16.9124, 4.4969, 2) (-17.2631, 2.87, 2) (-17.4777, 0.8824, 2)
extrude "Extrude4" cut sketch "Sketch4" against normal blind 3 contours A0 A1 L0 A2
